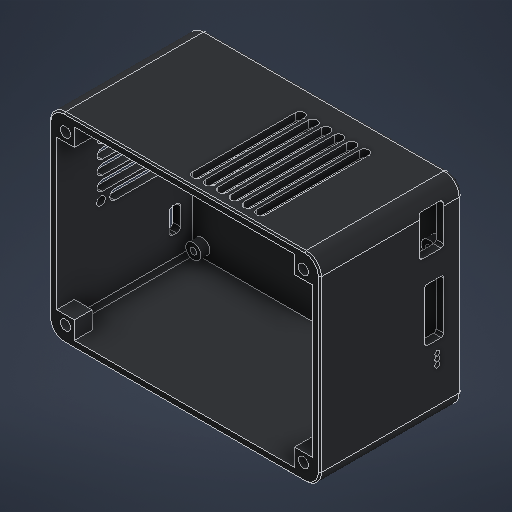
# Autodesk Inventor part: housing_bottom
Saved by Autodesk Inventor 2027.1 (Build 311270010, 270A)
## iProperties
Created: 2026-10-22
Part Number: housing_bottom
Material: 일반
Document SubType Name: Modeling
Designer: sungjun
Density: 1 g/cm^3
Appearance: housing_bottom_c
Author: sungjun
Autodesk Inventor part; units mm, degrees
ref_plane "작업 평면1" through (0, 0, 28.25) normal (0, 0, 1) x (1, 0, 0)
sketch "스케치1" plane through (0, 0, 28.25) normal (0, 0, 1) x (1, 0, 0)
  line L0 (0, 0) -> (107, 0)
  line L1 (107, 0) -> (107, 79)
  line L2 (107, 79) -> (0, 79)
  line L3 (0, 79) -> (0, 0)
  constraints: 8 end point, 2 parallel, 1 horizontal, 1 perpendicular
extrude "돌출1" add sketch "스케치1" along normal mid plane 56.5
fillet "모깎기1" radius 6 4 edges at (0, 0, 28.25) (0, 79, 28.25) (107, 79, 28.25) (107, 0, 28.25)
fillet "모깎기2" radius 1.5 8 edges at (105.2426, 1.7574, 0) (107, 39.5, 0) (53.5, 0, 0) (1.7574, 1.7574, 0) (0, 39.5, 0) (1.7574, 77.2426, 0) (53.5, 79, 0) (105.2426, 77.2426, 0)
chamfer "모따기1" distance 0.6 angle 45 8 edges at (0, 39.5, 56.5) (1.7574, 1.7574, 56.5) (53.5, 0, 56.5) (105.2426, 1.7574, 56.5) (107, 39.5, 56.5) (105.2426, 77.2426, 56.5) (53.5, 79, 56.5) (1.7574, 77.2426, 56.5)
ref_plane "작업 평면2" through (0, 0, 30.25) normal (0, 0, 1) x (1, 0, 0)
sketch "스케치2" plane through (0, 0, 30.25) normal (0, 0, 1) x (1, 0, 0)
  line L0 (3, 3) -> (104, 3)
  line L1 (104, 3) -> (104, 76)
  line L2 (104, 76) -> (3, 76)
  line L3 (3, 76) -> (3, 3)
  constraints: 8 end point, 2 parallel, 1 horizontal, 1 perpendicular
extrude "돌출2" cut sketch "스케치2" along normal mid plane 54.5
fillet "모깎기3" radius 1.5 4 edges at (104, 76, 29.75) (104, 3, 29.75) (3, 3, 29.75) (3, 76, 29.75)
ref_plane "작업 평면3" through (0, 0, 53) normal (0, 0, 1) x (1, 0, 0)
sketch "스케치3" plane through (0, 0, 53) normal (0, 0, 1) x (1, 0, 0)
  line L0 (3, 3) -> (10, 3)
  line L1 (10, 3) -> (10, 10)
  line L2 (10, 10) -> (3, 10)
  line L3 (3, 10) -> (3, 3)
  constraints: 8 end point, 2 parallel, 1 horizontal, 1 perpendicular
extrude "돌출3" add sketch "스케치3" along normal mid plane 7
ref_plane "작업 평면4" through (0, 0, 53) normal (0, 0, 1) x (1, 0, 0)
sketch "스케치4" plane through (0, 0, 53) normal (0, 0, 1) x (1, 0, 0)
  line L0 (97, 3) -> (104, 3)
  line L1 (104, 3) -> (104, 10)
  line L2 (104, 10) -> (97, 10)
  line L3 (97, 10) -> (97, 3)
  constraints: 8 end point, 2 parallel, 1 horizontal, 1 perpendicular
extrude "돌출4" add sketch "스케치4" along normal mid plane 7
ref_plane "작업 평면5" through (0, 0, 53) normal (0, 0, 1) x (1, 0, 0)
sketch "스케치5" plane through (0, 0, 53) normal (0, 0, 1) x (1, 0, 0)
  line L0 (3, 69) -> (10, 69)
  line L1 (10, 69) -> (10, 76)
  line L2 (10, 76) -> (3, 76)
  line L3 (3, 76) -> (3, 69)
  constraints: 8 end point, 2 parallel, 1 horizontal, 1 perpendicular
extrude "돌출5" add sketch "스케치5" along normal mid plane 7
ref_plane "작업 평면6" through (0, 0, 53) normal (0, 0, 1) x (1, 0, 0)
sketch "스케치6" plane through (0, 0, 53) normal (0, 0, 1) x (1, 0, 0)
  line L0 (97, 69) -> (104, 69)
  line L1 (104, 69) -> (104, 76)
  line L2 (104, 76) -> (97, 76)
  line L3 (97, 76) -> (97, 69)
  constraints: 8 end point, 2 parallel, 1 horizontal, 1 perpendicular
extrude "돌출6" add sketch "스케치6" along normal mid plane 7
ref_plane "작업 평면7" through (0, 0, 54) normal (0, 0, 1) x (1, 0, 0)
sketch "스케치7" plane through (0, 0, 54) normal (0, 0, 1) x (1, 0, 0)
  circle A0 centre (6.5, 6.5) radius 2
  constraints: 1 centre point
extrude "돌출7" cut sketch "스케치7" along normal mid plane 7
ref_plane "작업 평면8" through (0, 0, 54) normal (0, 0, 1) x (1, 0, 0)
sketch "스케치8" plane through (0, 0, 54) normal (0, 0, 1) x (1, 0, 0)
  circle A0 centre (100.5, 6.5) radius 2
  constraints: 1 centre point
extrude "돌출8" cut sketch "스케치8" along normal mid plane 7
ref_plane "작업 평면9" through (0, 0, 54) normal (0, 0, 1) x (1, 0, 0)
sketch "스케치9" plane through (0, 0, 54) normal (0, 0, 1) x (1, 0, 0)
  circle A0 centre (6.5, 72.5) radius 2
  constraints: 1 centre point
extrude "돌출9" cut sketch "스케치9" along normal mid plane 7
ref_plane "작업 평면10" through (0, 0, 54) normal (0, 0, 1) x (1, 0, 0)
sketch "스케치10" plane through (0, 0, 54) normal (0, 0, 1) x (1, 0, 0)
  circle A0 centre (100.5, 72.5) radius 2
  constraints: 1 centre point
extrude "돌출10" cut sketch "스케치10" along normal mid plane 7
ref_plane "작업 평면11" through (0, 0, 4.75) normal (0, 0, 1) x (1, 0, 0)
sketch "스케치11" plane through (0, 0, 4.75) normal (0, 0, 1) x (1, 0, 0)
  circle A0 centre (7, 7) radius 3
  constraints: 1 centre point
extrude "돌출11" add sketch "스케치11" along normal mid plane 3.5
ref_plane "작업 평면12" through (0, 0, 5.5) normal (0, 0, 1) x (1, 0, 0)
sketch "스케치12" plane through (0, 0, 5.5) normal (0, 0, 1) x (1, 0, 0)
  circle A0 centre (7, 7) radius 1.25
  constraints: 1 centre point
extrude "돌출12" cut sketch "스케치12" along normal mid plane 4
ref_plane "작업 평면13" through (0, 0, 4.75) normal (0, 0, 1) x (1, 0, 0)
sketch "스케치13" plane through (0, 0, 4.75) normal (0, 0, 1) x (1, 0, 0)
  circle A0 centre (100.1, 6.9) radius 3
  constraints: 1 centre point
extrude "돌출13" add sketch "스케치13" along normal mid plane 3.5
ref_plane "작업 평면14" through (0, 0, 5.5) normal (0, 0, 1) x (1, 0, 0)
sketch "스케치14" plane through (0, 0, 5.5) normal (0, 0, 1) x (1, 0, 0)
  circle A0 centre (100.1, 6.9) radius 1.25
  constraints: 1 centre point
extrude "돌출14" cut sketch "스케치14" along normal mid plane 4
ref_plane "작업 평면15" through (0, 0, 4.75) normal (0, 0, 1) x (1, 0, 0)
sketch "스케치15" plane through (0, 0, 4.75) normal (0, 0, 1) x (1, 0, 0)
  circle A0 centre (59.5, 37) radius 3
  constraints: 1 centre point
extrude "돌출15" add sketch "스케치15" along normal mid plane 3.5
ref_plane "작업 평면16" through (0, 0, 5.5) normal (0, 0, 1) x (1, 0, 0)
sketch "스케치16" plane through (0, 0, 5.5) normal (0, 0, 1) x (1, 0, 0)
  circle A0 centre (59.5, 37) radius 1.25
  constraints: 1 centre point
extrude "돌출16" cut sketch "스케치16" along normal mid plane 4
ref_plane "작업 평면17" through (0, 0, 4.75) normal (0, 0, 1) x (1, 0, 0)
sketch "스케치17" plane through (0, 0, 4.75) normal (0, 0, 1) x (1, 0, 0)
  circle A0 centre (100, 54.5) radius 3
  constraints: 1 centre point
extrude "돌출17" add sketch "스케치17" along normal mid plane 3.5
ref_plane "작업 평면18" through (0, 0, 5.5) normal (0, 0, 1) x (1, 0, 0)
sketch "스케치18" plane through (0, 0, 5.5) normal (0, 0, 1) x (1, 0, 0)
  circle A0 centre (100, 54.5) radius 1.25
  constraints: 1 centre point
extrude "돌출18" cut sketch "스케치18" along normal mid plane 4
ref_plane "작업 평면19" through (0, 0, 23) normal (0, 0, 1) x (1, 0, 0)
sketch "스케치19" plane through (0, 0, 23) normal (0, 0, 1) x (1, 0, 0)
  line L0 (-1, 41.5) -> (4, 41.5)
  line L1 (4, 41.5) -> (4, 45.5)
  line L2 (4, 45.5) -> (-1, 45.5)
  line L3 (-1, 45.5) -> (-1, 41.5)
  constraints: 8 end point, 2 parallel, 1 horizontal, 1 perpendicular
extrude "돌출19" cut sketch "스케치19" along normal mid plane 31
ref_plane "작업 평면20" through (1.5, 0, 0) normal (1, 0, 0) x (0, 1, 0)
sketch "스케치20" plane through (1.5, 0, 0) normal (1, 0, 0) x (0, 1, 0)
  circle A0 centre (43.5, 7.5) radius 2
  constraints: 1 centre point
extrude "돌출20" cut sketch "스케치20" along normal mid plane 5
ref_plane "작업 평면21" through (1.5, 0, 0) normal (1, 0, 0) x (0, 1, 0)
sketch "스케치21" plane through (1.5, 0, 0) normal (1, 0, 0) x (0, 1, 0)
  circle A0 centre (43.5, 38.5) radius 2
  constraints: 1 centre point
extrude "돌출21" cut sketch "스케치21" along normal mid plane 5
ref_plane "작업 평면22" through (0, 0, 23) normal (0, 0, 1) x (1, 0, 0)
sketch "스케치22" plane through (0, 0, 23) normal (0, 0, 1) x (1, 0, 0)
  line L0 (-1, 47) -> (4, 47)
  line L1 (4, 47) -> (4, 51)
  line L2 (4, 51) -> (-1, 51)
  line L3 (-1, 51) -> (-1, 47)
  constraints: 8 end point, 2 parallel, 1 horizontal, 1 perpendicular
extrude "돌출22" cut sketch "스케치22" along normal mid plane 31
ref_plane "작업 평면23" through (1.5, 0, 0) normal (1, 0, 0) x (0, 1, 0)
sketch "스케치23" plane through (1.5, 0, 0) normal (1, 0, 0) x (0, 1, 0)
  circle A0 centre (49, 7.5) radius 2
  constraints: 1 centre point
extrude "돌출23" cut sketch "스케치23" along normal mid plane 5
ref_plane "작업 평면24" through (1.5, 0, 0) normal (1, 0, 0) x (0, 1, 0)
sketch "스케치24" plane through (1.5, 0, 0) normal (1, 0, 0) x (0, 1, 0)
  circle A0 centre (49, 38.5) radius 2
  constraints: 1 centre point
extrude "돌출24" cut sketch "스케치24" along normal mid plane 5
ref_plane "작업 평면25" through (0, 0, 23) normal (0, 0, 1) x (1, 0, 0)
sketch "스케치25" plane through (0, 0, 23) normal (0, 0, 1) x (1, 0, 0)
  line L0 (-1, 52.5) -> (4, 52.5)
  line L1 (4, 52.5) -> (4, 56.5)
  line L2 (4, 56.5) -> (-1, 56.5)
  line L3 (-1, 56.5) -> (-1, 52.5)
  constraints: 8 end point, 2 parallel, 1 horizontal, 1 perpendicular
extrude "돌출25" cut sketch "스케치25" along normal mid plane 31
ref_plane "작업 평면26" through (1.5, 0, 0) normal (1, 0, 0) x (0, 1, 0)
sketch "스케치26" plane through (1.5, 0, 0) normal (1, 0, 0) x (0, 1, 0)
  circle A0 centre (54.5, 7.5) radius 2
  constraints: 1 centre point
extrude "돌출26" cut sketch "스케치26" along normal mid plane 5
ref_plane "작업 평면27" through (1.5, 0, 0) normal (1, 0, 0) x (0, 1, 0)
sketch "스케치27" plane through (1.5, 0, 0) normal (1, 0, 0) x (0, 1, 0)
  circle A0 centre (54.5, 38.5) radius 2
  constraints: 1 centre point
extrude "돌출27" cut sketch "스케치27" along normal mid plane 5
ref_plane "작업 평면28" through (0, 0, 23) normal (0, 0, 1) x (1, 0, 0)
sketch "스케치28" plane through (0, 0, 23) normal (0, 0, 1) x (1, 0, 0)
  line L0 (-1, 58) -> (4, 58)
  line L1 (4, 58) -> (4, 62)
  line L2 (4, 62) -> (-1, 62)
  line L3 (-1, 62) -> (-1, 58)
  constraints: 8 end point, 2 parallel, 1 horizontal, 1 perpendicular
extrude "돌출28" cut sketch "스케치28" along normal mid plane 31
ref_plane "작업 평면29" through (1.5, 0, 0) normal (1, 0, 0) x (0, 1, 0)
sketch "스케치29" plane through (1.5, 0, 0) normal (1, 0, 0) x (0, 1, 0)
  circle A0 centre (60, 7.5) radius 2
  constraints: 1 centre point
extrude "돌출29" cut sketch "스케치29" along normal mid plane 5
ref_plane "작업 평면30" through (1.5, 0, 0) normal (1, 0, 0) x (0, 1, 0)
sketch "스케치30" plane through (1.5, 0, 0) normal (1, 0, 0) x (0, 1, 0)
  circle A0 centre (60, 38.5) radius 2
  constraints: 1 centre point
extrude "돌출30" cut sketch "스케치30" along normal mid plane 5
ref_plane "작업 평면31" through (0, 0, 23) normal (0, 0, 1) x (1, 0, 0)
sketch "스케치31" plane through (0, 0, 23) normal (0, 0, 1) x (1, 0, 0)
  line L0 (-1, 63.5) -> (4, 63.5)
  line L1 (4, 63.5) -> (4, 67.5)
  line L2 (4, 67.5) -> (-1, 67.5)
  line L3 (-1, 67.5) -> (-1, 63.5)
  constraints: 8 end point, 2 parallel, 1 horizontal, 1 perpendicular
extrude "돌출31" cut sketch "스케치31" along normal mid plane 31
ref_plane "작업 평면32" through (1.5, 0, 0) normal (1, 0, 0) x (0, 1, 0)
sketch "스케치32" plane through (1.5, 0, 0) normal (1, 0, 0) x (0, 1, 0)
  circle A0 centre (65.5, 7.5) radius 2
  constraints: 1 centre point
extrude "돌출32" cut sketch "스케치32" along normal mid plane 5
ref_plane "작업 평면33" through (1.5, 0, 0) normal (1, 0, 0) x (0, 1, 0)
sketch "스케치33" plane through (1.5, 0, 0) normal (1, 0, 0) x (0, 1, 0)
  circle A0 centre (65.5, 38.5) radius 2
  constraints: 1 centre point
extrude "돌출33" cut sketch "스케치33" along normal mid plane 5
ref_plane "작업 평면34" through (0, 0, 23) normal (0, 0, 1) x (1, 0, 0)
sketch "스케치34" plane through (0, 0, 23) normal (0, 0, 1) x (1, 0, 0)
  line L0 (-1, 36) -> (4, 36)
  line L1 (4, 36) -> (4, 40)
  line L2 (4, 40) -> (-1, 40)
  line L3 (-1, 40) -> (-1, 36)
  constraints: 8 end point, 2 parallel, 1 horizontal, 1 perpendicular
extrude "돌출34" cut sketch "스케치34" along normal mid plane 21
ref_plane "작업 평면35" through (1.5, 0, 0) normal (1, 0, 0) x (0, 1, 0)
sketch "스케치35" plane through (1.5, 0, 0) normal (1, 0, 0) x (0, 1, 0)
  circle A0 centre (38, 12.5) radius 2
  constraints: 1 centre point
extrude "돌출35" cut sketch "스케치35" along normal mid plane 5
ref_plane "작업 평면36" through (1.5, 0, 0) normal (1, 0, 0) x (0, 1, 0)
sketch "스케치36" plane through (1.5, 0, 0) normal (1, 0, 0) x (0, 1, 0)
  circle A0 centre (38, 33.5) radius 2
  constraints: 1 centre point
extrude "돌출36" cut sketch "스케치36" along normal mid plane 5
ref_plane "작업 평면37" through (0, 0, 23) normal (0, 0, 1) x (1, 0, 0)
sketch "스케치37" plane through (0, 0, 23) normal (0, 0, 1) x (1, 0, 0)
  line L0 (-1, 69) -> (4, 69)
  line L1 (4, 69) -> (4, 73)
  line L2 (4, 73) -> (-1, 73)
  line L3 (-1, 73) -> (-1, 69)
  constraints: 8 end point, 2 parallel, 1 horizontal, 1 perpendicular
extrude "돌출37" cut sketch "스케치37" along normal mid plane 21
ref_plane "작업 평면38" through (1.5, 0, 0) normal (1, 0, 0) x (0, 1, 0)
sketch "스케치38" plane through (1.5, 0, 0) normal (1, 0, 0) x (0, 1, 0)
  circle A0 centre (71, 12.5) radius 2
  constraints: 1 centre point
extrude "돌출38" cut sketch "스케치38" along normal mid plane 5
ref_plane "작업 평면39" through (1.5, 0, 0) normal (1, 0, 0) x (0, 1, 0)
sketch "스케치39" plane through (1.5, 0, 0) normal (1, 0, 0) x (0, 1, 0)
  circle A0 centre (71, 33.5) radius 2
  constraints: 1 centre point
extrude "돌출39" cut sketch "스케치39" along normal mid plane 5
ref_plane "작업 평면40" through (1.5, 0, 0) normal (1, 0, 0) x (0, 1, 0)
sketch "스케치40" plane through (1.5, 0, 0) normal (1, 0, 0) x (0, 1, 0)
  circle A0 centre (38.5, 7) radius 1.7
  constraints: 1 centre point
extrude "돌출40" cut sketch "스케치40" along normal mid plane 5
ref_plane "작업 평면41" through (1.5, 0, 0) normal (1, 0, 0) x (0, 1, 0)
sketch "스케치41" plane through (1.5, 0, 0) normal (1, 0, 0) x (0, 1, 0)
  circle A0 centre (38.5, 39) radius 1.7
  constraints: 1 centre point
extrude "돌출41" cut sketch "스케치41" along normal mid plane 5
ref_plane "작업 평면42" through (1.5, 0, 0) normal (1, 0, 0) x (0, 1, 0)
sketch "스케치42" plane through (1.5, 0, 0) normal (1, 0, 0) x (0, 1, 0)
  circle A0 centre (70.5, 7) radius 1.7
  constraints: 1 centre point
extrude "돌출42" cut sketch "스케치42" along normal mid plane 5
ref_plane "작업 평면43" through (1.5, 0, 0) normal (1, 0, 0) x (0, 1, 0)
sketch "스케치43" plane through (1.5, 0, 0) normal (1, 0, 0) x (0, 1, 0)
  circle A0 centre (70.5, 39) radius 1.7
  constraints: 1 centre point
extrude "돌출43" cut sketch "스케치43" along normal mid plane 5
ref_plane "작업 평면44" through (0, 0, 31.3) normal (0, 0, 1) x (1, 0, 0)
sketch "스케치44" plane through (0, 0, 31.3) normal (0, 0, 1) x (1, 0, 0)
  line L0 (51.7, 75) -> (55.3, 75)
  line L1 (55.3, 75) -> (55.3, 80)
  line L2 (55.3, 80) -> (51.7, 80)
  line L3 (51.7, 80) -> (51.7, 75)
  constraints: 8 end point, 2 parallel, 1 horizontal, 1 perpendicular
extrude "돌출44" cut sketch "스케치44" along normal mid plane 40.8
ref_plane "작업 평면45" through (0, 77.5, 0) normal (0, 1, 0) x (-1, 0, 0)
sketch "스케치45" plane through (0, 77.5, 0) normal (0, 1, 0) x (-1, 0, 0)
  circle A0 centre (-53.5, 10.9) radius 1.8
  constraints: 1 centre point
extrude "돌출45" cut sketch "스케치45" along normal mid plane 5
ref_plane "작업 평면46" through (0, 77.5, 0) normal (0, 1, 0) x (-1, 0, 0)
sketch "스케치46" plane through (0, 77.5, 0) normal (0, 1, 0) x (-1, 0, 0)
  circle A0 centre (-53.5, 51.7) radius 1.8
  constraints: 1 centre point
extrude "돌출46" cut sketch "스케치46" along normal mid plane 5
ref_plane "작업 평면47" through (0, 0, 31.3) normal (0, 0, 1) x (1, 0, 0)
sketch "스케치47" plane through (0, 0, 31.3) normal (0, 0, 1) x (1, 0, 0)
  line L0 (56.8, 75) -> (60.4, 75)
  line L1 (60.4, 75) -> (60.4, 80)
  line L2 (60.4, 80) -> (56.8, 80)
  line L3 (56.8, 80) -> (56.8, 75)
  constraints: 8 end point, 2 parallel, 1 horizontal, 1 perpendicular
extrude "돌출47" cut sketch "스케치47" along normal mid plane 40.8
ref_plane "작업 평면48" through (0, 77.5, 0) normal (0, 1, 0) x (-1, 0, 0)
sketch "스케치48" plane through (0, 77.5, 0) normal (0, 1, 0) x (-1, 0, 0)
  circle A0 centre (-58.6, 10.9) radius 1.8
  constraints: 1 centre point
extrude "돌출48" cut sketch "스케치48" along normal mid plane 5
ref_plane "작업 평면49" through (0, 77.5, 0) normal (0, 1, 0) x (-1, 0, 0)
sketch "스케치49" plane through (0, 77.5, 0) normal (0, 1, 0) x (-1, 0, 0)
  circle A0 centre (-58.6, 51.7) radius 1.8
  constraints: 1 centre point
extrude "돌출49" cut sketch "스케치49" along normal mid plane 5
ref_plane "작업 평면50" through (0, 0, 31.3) normal (0, 0, 1) x (1, 0, 0)
sketch "스케치50" plane through (0, 0, 31.3) normal (0, 0, 1) x (1, 0, 0)
  line L0 (61.9, 75) -> (65.5, 75)
  line L1 (65.5, 75) -> (65.5, 80)
  line L2 (65.5, 80) -> (61.9, 80)
  line L3 (61.9, 80) -> (61.9, 75)
  constraints: 8 end point, 2 parallel, 1 horizontal, 1 perpendicular
extrude "돌출50" cut sketch "스케치50" along normal mid plane 40.8
ref_plane "작업 평면51" through (0, 77.5, 0) normal (0, 1, 0) x (-1, 0, 0)
sketch "스케치51" plane through (0, 77.5, 0) normal (0, 1, 0) x (-1, 0, 0)
  circle A0 centre (-63.7, 10.9) radius 1.8
  constraints: 1 centre point
extrude "돌출51" cut sketch "스케치51" along normal mid plane 5
ref_plane "작업 평면52" through (0, 77.5, 0) normal (0, 1, 0) x (-1, 0, 0)
sketch "스케치52" plane through (0, 77.5, 0) normal (0, 1, 0) x (-1, 0, 0)
  circle A0 centre (-63.7, 51.7) radius 1.8
  constraints: 1 centre point
extrude "돌출52" cut sketch "스케치52" along normal mid plane 5
ref_plane "작업 평면53" through (0, 0, 31.3) normal (0, 0, 1) x (1, 0, 0)
sketch "스케치53" plane through (0, 0, 31.3) normal (0, 0, 1) x (1, 0, 0)
  line L0 (67, 75) -> (70.6, 75)
  line L1 (70.6, 75) -> (70.6, 80)
  line L2 (70.6, 80) -> (67, 80)
  line L3 (67, 80) -> (67, 75)
  constraints: 8 end point, 2 parallel, 1 horizontal, 1 perpendicular
extrude "돌출53" cut sketch "스케치53" along normal mid plane 40.8
ref_plane "작업 평면54" through (0, 77.5, 0) normal (0, 1, 0) x (-1, 0, 0)
sketch "스케치54" plane through (0, 77.5, 0) normal (0, 1, 0) x (-1, 0, 0)
  circle A0 centre (-68.8, 10.9) radius 1.8
  constraints: 1 centre point
extrude "돌출54" cut sketch "스케치54" along normal mid plane 5
ref_plane "작업 평면55" through (0, 77.5, 0) normal (0, 1, 0) x (-1, 0, 0)
sketch "스케치55" plane through (0, 77.5, 0) normal (0, 1, 0) x (-1, 0, 0)
  circle A0 centre (-68.8, 51.7) radius 1.8
  constraints: 1 centre point
extrude "돌출55" cut sketch "스케치55" along normal mid plane 5
ref_plane "작업 평면56" through (0, 0, 31.3) normal (0, 0, 1) x (1, 0, 0)
sketch "스케치56" plane through (0, 0, 31.3) normal (0, 0, 1) x (1, 0, 0)
  line L0 (72.1, 75) -> (75.7, 75)
  line L1 (75.7, 75) -> (75.7, 80)
  line L2 (75.7, 80) -> (72.1, 80)
  line L3 (72.1, 80) -> (72.1, 75)
  constraints: 8 end point, 2 parallel, 1 horizontal, 1 perpendicular
extrude "돌출56" cut sketch "스케치56" along normal mid plane 40.8
ref_plane "작업 평면57" through (0, 77.5, 0) normal (0, 1, 0) x (-1, 0, 0)
sketch "스케치57" plane through (0, 77.5, 0) normal (0, 1, 0) x (-1, 0, 0)
  circle A0 centre (-73.9, 10.9) radius 1.8
  constraints: 1 centre point
extrude "돌출57" cut sketch "스케치57" along normal mid plane 5
ref_plane "작업 평면58" through (0, 77.5, 0) normal (0, 1, 0) x (-1, 0, 0)
sketch "스케치58" plane through (0, 77.5, 0) normal (0, 1, 0) x (-1, 0, 0)
  circle A0 centre (-73.9, 51.7) radius 1.8
  constraints: 1 centre point
extrude "돌출58" cut sketch "스케치58" along normal mid plane 5
ref_plane "작업 평면59" through (0, 0, 31.3) normal (0, 0, 1) x (1, 0, 0)
sketch "스케치59" plane through (0, 0, 31.3) normal (0, 0, 1) x (1, 0, 0)
  line L0 (77.2, 75) -> (80.8, 75)
  line L1 (80.8, 75) -> (80.8, 80)
  line L2 (80.8, 80) -> (77.2, 80)
  line L3 (77.2, 80) -> (77.2, 75)
  constraints: 8 end point, 2 parallel, 1 horizontal, 1 perpendicular
extrude "돌출59" cut sketch "스케치59" along normal mid plane 40.8
ref_plane "작업 평면60" through (0, 77.5, 0) normal (0, 1, 0) x (-1, 0, 0)
sketch "스케치60" plane through (0, 77.5, 0) normal (0, 1, 0) x (-1, 0, 0)
  circle A0 centre (-79, 10.9) radius 1.8
  constraints: 1 centre point
extrude "돌출60" cut sketch "스케치60" along normal mid plane 5
ref_plane "작업 평면61" through (0, 77.5, 0) normal (0, 1, 0) x (-1, 0, 0)
sketch "스케치61" plane through (0, 77.5, 0) normal (0, 1, 0) x (-1, 0, 0)
  circle A0 centre (-79, 51.7) radius 1.8
  constraints: 1 centre point
extrude "돌출61" cut sketch "스케치61" along normal mid plane 5
ref_plane "작업 평면62" through (0, 0, 4.65) normal (0, 0, 1) x (1, 0, 0)
sketch "스케치62" plane through (0, 0, 4.65) normal (0, 0, 1) x (1, 0, 0)
  line L0 (23.2, 32.3) -> (24.4, 32.3)
  line L1 (24.4, 32.3) -> (24.4, 76)
  line L2 (24.4, 76) -> (23.2, 76)
  line L3 (23.2, 76) -> (23.2, 32.3)
  constraints: 8 end point, 2 parallel, 1 horizontal, 1 perpendicular
extrude "돌출62" add sketch "스케치62" along normal mid plane 3.3
ref_plane "작업 평면63" through (0, 0, 4.65) normal (0, 0, 1) x (1, 0, 0)
sketch "스케치63" plane through (0, 0, 4.65) normal (0, 0, 1) x (1, 0, 0)
  line L0 (3, 32.3) -> (24.4, 32.3)
  line L1 (24.4, 32.3) -> (24.4, 33.5)
  line L2 (24.4, 33.5) -> (3, 33.5)
  line L3 (3, 33.5) -> (3, 32.3)
  constraints: 8 end point, 2 parallel, 1 horizontal, 1 perpendicular
extrude "돌출63" add sketch "스케치63" along normal mid plane 3.3
ref_plane "작업 평면64" through (0, 0, 9.85) normal (0, 0, 1) x (1, 0, 0)
sketch "스케치64" plane through (0, 0, 9.85) normal (0, 0, 1) x (1, 0, 0)
  line L0 (-1, 12.5) -> (4, 12.5)
  line L1 (4, 12.5) -> (4, 22.5)
  line L2 (4, 22.5) -> (-1, 22.5)
  line L3 (-1, 22.5) -> (-1, 12.5)
  constraints: 8 end point, 2 parallel, 1 horizontal, 1 perpendicular
extrude "돌출64" cut sketch "스케치64" along normal mid plane 4.5
fillet "모깎기4" radius 1.5 4 edges at (1.5, 12.5, 12.1) (1.5, 22.5, 12.1) (1.5, 22.5, 7.6) (1.5, 12.5, 7.6)
ref_plane "작업 평면65" through (0, 0, 12.35) normal (0, 0, 1) x (1, 0, 0)
sketch "스케치65" plane through (0, 0, 12.35) normal (0, 0, 1) x (1, 0, 0)
  line L0 (103, 59.1) -> (108, 59.1)
  line L1 (108, 59.1) -> (108, 75.1)
  line L2 (108, 75.1) -> (103, 75.1)
  line L3 (103, 75.1) -> (103, 59.1)
  constraints: 8 end point, 2 parallel, 1 horizontal, 1 perpendicular
extrude "돌출65" cut sketch "스케치65" along normal mid plane 9.5
fillet "모깎기5" radius 1 4 edges at (105.2476, 75.1, 17.1) (105.5, 59.1, 17.1) (105.5, 59.1, 7.6) (105.2476, 75.1, 7.6)
ref_plane "작업 평면66" through (0, 0, 11.35) normal (0, 0, 1) x (1, 0, 0)
sketch "스케치66" plane through (0, 0, 11.35) normal (0, 0, 1) x (1, 0, 0)
  line L0 (103, 28.5) -> (108, 28.5)
  line L1 (108, 28.5) -> (108, 49.5)
  line L2 (108, 49.5) -> (103, 49.5)
  line L3 (103, 49.5) -> (103, 28.5)
  constraints: 8 end point, 2 parallel, 1 horizontal, 1 perpendicular
extrude "돌출66" cut sketch "스케치66" along normal mid plane 7.5
fillet "모깎기6" radius 1 4 edges at (105.5, 49.5, 15.1) (105.5, 28.5, 15.1) (105.5, 28.5, 7.6) (105.5, 49.5, 7.6)
ref_plane "작업 평면67" through (105.5, 0, 0) normal (1, 0, 0) x (0, 1, 0)
sketch "스케치67" plane through (105.5, 0, 0) normal (1, 0, 0) x (0, 1, 0)
  circle A0 centre (19.9, 10.1) radius 1
  constraints: 1 centre point
extrude "돌출67" cut sketch "스케치67" along normal mid plane 5
ref_plane "작업 평면68" through (105.5, 0, 0) normal (1, 0, 0) x (0, 1, 0)
sketch "스케치68" plane through (105.5, 0, 0) normal (1, 0, 0) x (0, 1, 0)
  circle A0 centre (21.9, 10.1) radius 1
  constraints: 1 centre point
extrude "돌출68" cut sketch "스케치68" along normal mid plane 5
ref_plane "작업 평면69" through (105.5, 0, 0) normal (1, 0, 0) x (0, 1, 0)
sketch "스케치69" plane through (105.5, 0, 0) normal (1, 0, 0) x (0, 1, 0)
  circle A0 centre (23.9, 10.1) radius 1
  constraints: 1 centre point
extrude "돌출69" cut sketch "스케치69" along normal mid plane 5
ref_plane "작업 평면70" through (0, 0, 0) normal (0, 0, 1) x (1, 0, 0)
sketch "스케치70" plane through (0, 0, 0) normal (0, 0, 1) x (1, 0, 0)
  circle A0 centre (12, 12) radius 4.5
  constraints: 1 centre point
extrude "돌출70" cut sketch "스케치70" along normal mid plane 2
ref_plane "작업 평면71" through (0, 0, 0) normal (0, 0, 1) x (1, 0, 0)
sketch "스케치71" plane through (0, 0, 0) normal (0, 0, 1) x (1, 0, 0)
  circle A0 centre (12, 67) radius 4.5
  constraints: 1 centre point
extrude "돌출71" cut sketch "스케치71" along normal mid plane 2
ref_plane "작업 평면72" through (0, 0, 0) normal (0, 0, 1) x (1, 0, 0)
sketch "스케치72" plane through (0, 0, 0) normal (0, 0, 1) x (1, 0, 0)
  circle A0 centre (95, 12) radius 4.5
  constraints: 1 centre point
extrude "돌출72" cut sketch "스케치72" along normal mid plane 2
ref_plane "작업 평면73" through (0, 0, 0) normal (0, 0, 1) x (1, 0, 0)
sketch "스케치73" plane through (0, 0, 0) normal (0, 0, 1) x (1, 0, 0)
  circle A0 centre (95, 67) radius 4.5
  constraints: 1 centre point
extrude "돌출73" cut sketch "스케치73" along normal mid plane 2
